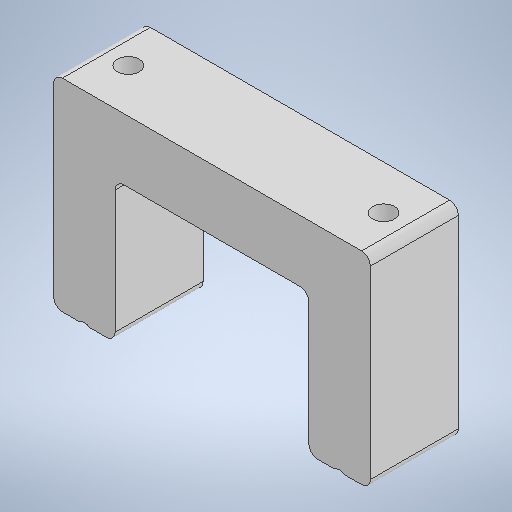
# Autodesk Inventor part: AP10.0_com
Saved by Autodesk Inventor 2025.3 (Build 293356030, 356C)
## iProperties
Created: 2025-08-02
Part Number: AP10.0_com
Material: 一般
Document SubType Name: Modeling
Designer: ibuki_ono
Density: 1 g/cm^3
Appearance: 既定
Author: ibuki_ono
Autodesk Inventor part; units mm, degrees
ref_plane "YZ Plane" through (0, 0, 0) normal (1, 0, 0) x (0, 1, 0)
ref_plane "XZ Plane" through (0, 0, 0) normal (0, 1, 0) x (-1, 0, 0)
ref_plane "XY Plane" through (0, 0, 0) normal (0, 0, 1) x (1, 0, 0)
sketch "スケッチ1" plane through (0, 0, 0) normal (0, 0, 1) x (1, 0, 0)
  line L0 (-11, -8) -> (11, -8)
  line L1 (11, -8) -> (11, 8)
  line L2 (11, 8) -> (-11, 8)
  line L3 (-11, 8) -> (-11, -8)
  line L4 (-11, -8) -> (11, 8) construction
  line L5 (11, -8) -> (-11, 8) construction
  line L6 (-18, 15) -> (18, 15)
  line L7 (18, 15) -> (18, -15)
  line L8 (18, -15) -> (-18, -15)
  line L9 (-18, -15) -> (-18, 15)
  line L10 (-18, -8) -> (18, -8)
  point P0 (0, 0)
  dimension "d0" = 22
  dimension "d1" = 16
  dimension "d2" = 7
  constraints: 22 end point, 4 parallel, 3 perpendicular, 2 midpoint, 2 point on line, 1 collinear, 1 horizontal, 3 other
  measures "d0" distance of L2.end L1.end
  measures "d1" distance of L1.end L0.end
  measures "d2" distance between parallel lines of L2 L6
extrude "押し出し1" add sketch "スケッチ1" along normal mid plane 10 contours L10 L9 L6 L7 L1 L2 L3
sketch "スケッチ2" plane through (0, 0, 5) normal (0, 0, 1) x (1, 0, 0)
  line L0 (-18, -8) -> (-11, -8) projected
  line L1 (11, -8) -> (18, -8) projected
  circle A0 centre (-14.5, -8.85) radius 1.05
  circle A1 centre (14.5, -8.85) radius 1.05
  point P0 (0, 0)
  point P1 (-14.5, -8)
  point P2 (14.5, -8)
  point P3 (15.1164, -8)
  point P4 (13.8836, -8)
  point P5 (-13.8836, -8)
  point P6 (-15.1164, -8)
  dimension "d5" = 2.1
  dimension "d6" = 2.1
  dimension "d7" = 0.85
  dimension "d8" = 0.85
  constraints: 2 centre point, 2 midpoint, 2 vertical alignment
  measures "d5" diameter of A0
  measures "d6" diameter of A1
  measures "d7" distance from line of L0 A0.centre
  measures "d8" distance from line of L1 A1.centre
extrude "押し出し2" cut sketch "スケッチ2" against normal through all contours A0 L0 | A1 L1 picked at (-14.6422, -7.9635) picked at (14.3578, -7.9635)
sketch "スケッチ3" plane through (-11, -8, -5) normal (0, -1, 0) x (1, 0, 0)
  line L0 (-2.8836, 0) -> (-4.1164, 0) projected
  line L1 (-2.8836, 10) -> (-2.8836, 0) projected
  line L2 (-4.1164, 10) -> (-2.8836, 10) projected
  line L3 (-4.1164, 0) -> (-4.1164, 10) projected
  line L4 (26.1164, 0) -> (24.8836, 0) projected
  line L5 (26.1164, 10) -> (26.1164, 0) projected
  line L6 (24.8836, 10) -> (26.1164, 10) projected
  line L7 (24.8836, 0) -> (24.8836, 10) projected
  line L8 (29, 10) -> (-7, 10) construction
  line L9 (-3.5, 10) -> (-3.5, 0) construction
  line L10 (25.5, 0) -> (25.5, 10) construction
  point P0 (11, 5)
  point P1 (-3.5, 5)
  point P2 (25.5, 5)
  constraints: 4 end point, 4 midpoint, 2 point on line, 1 perpendicular
hole "穴1" at (-14.5, -8, 0) at (14.5, -8, 0) direction (0, 1, 0) diameter 2.5 end through all
fillet "フィレット1" radius 1 8 edges at (-18, 15, 0) (18, 15, 0) (18, -8, 0) (11, -8, 0) (-11, -8, 0) (-18, -8, 0) (-11, 8, 0) (11, 8, 0)
equation "\"d8\" = d7"
